Autodesk Fusion 360 part; units mm, degrees
(part 2 of 3)
sketch "Skizze2 (7)" plane through (0, 0, 263) normal (0, 0, 1) x (1, 0, 0) in component "Rear_thread_plate_left_0.15"
  circle A0 centre (22, 84) radius 2.1
  dimension "d573" = 22
  dimension "d574" = 84
  dimension "d575" = 4.2
  measures "d573" horizontal distance of origin A0.centre
  measures "d574" vertical distance of origin A0.centre
  measures "d575" diameter of A0
extrude "M5_pilot_not_thread_geometry" cut sketch "Skizze2 (7)" along normal blind 5 bodies 24 in component "Rear_thread_plate_left_0.15"
ref_plane "Arbeitsebene3" through (0, 0, 263) normal (0, 0, 1) x (1, 0, 0) in component "Rear_thread_plate_left_0.15"
sketch "Skizze3 (9)" plane through (0, 0, 263) normal (0, 0, 1) x (1, 0, 0) in component "Rear_thread_plate_left_0.15"
  circle A0 centre (22, 72) radius 1.5
  dimension "d580" = 22
  dimension "d581" = 72
  dimension "d582" = 3
  measures "d580" horizontal distance of origin A0.centre
  measures "d581" vertical distance of origin A0.centre
  measures "d582" diameter of A0
extrude "Retainer_bore" cut sketch "Skizze3 (9)" along normal blind 5 bodies 24 in component "Rear_thread_plate_left_0.15"
ref_plane "Arbeitsebene4" through (0, 0, 263) normal (0, 0, 1) x (1, 0, 0) in component "Rear_thread_plate_left_0.15"
sketch "Skizze4 (6)" plane through (0, 0, 263) normal (0, 0, 1) x (1, 0, 0) in component "Rear_thread_plate_left_0.15"
  circle A0 centre (22, 96) radius 1.5
  dimension "d587" = 22
  dimension "d588" = 96
  dimension "d589" = 3
  measures "d587" horizontal distance of origin A0.centre
  measures "d588" vertical distance of origin A0.centre
  measures "d589" diameter of A0
extrude "Retainer_bore (1)" cut sketch "Skizze4 (6)" along normal blind 5 bodies 24 in component "Rear_thread_plate_left_0.15"
ref_plane "Arbeitsebene3" through (0, 0, 288) normal (0, 0, 1) x (1, 0, 0) in component "Rear_removable"
sketch "Skizze4 (7)" plane through (0, 0, 288) normal (0, 0, 1) x (1, 0, 0) in component "Rear_removable"
  circle A0 centre (22, 280) radius 2.75
  dimension "d594" = 22
  dimension "d595" = 280
  dimension "d596" = 5.5
  measures "d594" horizontal distance of origin A0.centre
  measures "d595" vertical distance of origin A0.centre
  measures "d596" diameter of A0
extrude "Rear_M5_through_left_0.5" cut sketch "Skizze4 (7)" along normal blind 12 bodies 6 in component "Rear_removable"
ref_plane "Arbeitsebene3" through (0, 0, 268) normal (0, 0, 1) x (1, 0, 0) in component "Rear_cleat_left"
sketch "Skizze4 (8)" plane through (0, 0, 268) normal (0, 0, 1) x (1, 0, 0) in component "Rear_cleat_left"
  circle A0 centre (22, 280) radius 2.75
  dimension "d601" = 22
  dimension "d602" = 280
  dimension "d603" = 5.5
  measures "d601" horizontal distance of origin A0.centre
  measures "d602" vertical distance of origin A0.centre
  measures "d603" diameter of A0
ref_plane "Arbeitsebene1" through (0, 0, 263) normal (0, 0, 1) x (1, 0, 0) in component "Rear_thread_plate_left_0.5"
sketch "Skizze1 (22)" plane through (0, 0, 263) normal (0, 0, 1) x (1, 0, 0) in component "Rear_thread_plate_left_0.5"
  line L0 (12, 260) -> (32, 260)
  line L1 (32, 260) -> (32, 300)
  line L2 (32, 300) -> (12, 300)
  line L3 (12, 300) -> (12, 260)
  dimension "d608" = 12
  dimension "d609" = 260
  dimension "d610" = 20
  dimension "d611" = 40
  constraint horizontal L0
  constraint horizontal L2
  constraint vertical L1
  constraint vertical L3
  measures "d608" horizontal distance of origin L0.start
  measures "d609" vertical distance of origin L0.start
  measures "d610" horizontal distance of L0.start L0.end
  measures "d611" vertical distance of L0.end L1.end
extrude "Steel_plate_M5_tap_after_drilling'" add sketch "Skizze1 (22)" along normal blind 5 separate body makes body 25 in component "Rear_thread_plate_left_0.5"
ref_plane "Arbeitsebene2" through (0, 0, 263) normal (0, 0, 1) x (1, 0, 0) in component "Rear_thread_plate_left_0.5"
sketch "Skizze2 (8)" plane through (0, 0, 263) normal (0, 0, 1) x (1, 0, 0) in component "Rear_thread_plate_left_0.5"
  circle A0 centre (22, 280) radius 2.1
  dimension "d616" = 22
  dimension "d617" = 280
  dimension "d618" = 4.2
  measures "d616" horizontal distance of origin A0.centre
  measures "d617" vertical distance of origin A0.centre
  measures "d618" diameter of A0
extrude "M5_pilot_not_thread_geometry'" cut sketch "Skizze2 (8)" along normal blind 5 bodies 25 in component "Rear_thread_plate_left_0.5"
ref_plane "Arbeitsebene3" through (0, 0, 263) normal (0, 0, 1) x (1, 0, 0) in component "Rear_thread_plate_left_0.5"
sketch "Skizze3 (10)" plane through (0, 0, 263) normal (0, 0, 1) x (1, 0, 0) in component "Rear_thread_plate_left_0.5"
  circle A0 centre (22, 268) radius 1.5
  dimension "d623" = 22
  dimension "d624" = 268
  dimension "d625" = 3
  measures "d623" horizontal distance of origin A0.centre
  measures "d624" vertical distance of origin A0.centre
  measures "d625" diameter of A0
extrude "Retainer_bore'" cut sketch "Skizze3 (10)" along normal blind 5 bodies 25 in component "Rear_thread_plate_left_0.5"
ref_plane "Arbeitsebene4" through (0, 0, 263) normal (0, 0, 1) x (1, 0, 0) in component "Rear_thread_plate_left_0.5"
sketch "Skizze4 (9)" plane through (0, 0, 263) normal (0, 0, 1) x (1, 0, 0) in component "Rear_thread_plate_left_0.5"
  circle A0 centre (22, 292) radius 1.5
  dimension "d630" = 22
  dimension "d631" = 292
  dimension "d632" = 3
  measures "d630" horizontal distance of origin A0.centre
  measures "d631" vertical distance of origin A0.centre
  measures "d632" diameter of A0
extrude "Retainer_bore (1)'" cut sketch "Skizze4 (9)" along normal blind 5 bodies 25 in component "Rear_thread_plate_left_0.5"
ref_plane "Arbeitsebene4" through (0, 0, 288) normal (0, 0, 1) x (1, 0, 0) in component "Rear_removable"
sketch "Skizze5 (4)" plane through (0, 0, 288) normal (0, 0, 1) x (1, 0, 0) in component "Rear_removable"
  circle A0 centre (22, 476) radius 2.75
  dimension "d637" = 22
  dimension "d638" = 476
  dimension "d639" = 5.5
  measures "d637" horizontal distance of origin A0.centre
  measures "d638" vertical distance of origin A0.centre
  measures "d639" diameter of A0
extrude "Rear_M5_through_left_0.85" cut sketch "Skizze5 (4)" along normal blind 12 bodies 6 in component "Rear_removable"
ref_plane "Arbeitsebene4" through (0, 0, 268) normal (0, 0, 1) x (1, 0, 0) in component "Rear_cleat_left"
sketch "Skizze5 (5)" plane through (0, 0, 268) normal (0, 0, 1) x (1, 0, 0) in component "Rear_cleat_left"
  circle A0 centre (22, 476) radius 2.75
  dimension "d644" = 22
  dimension "d645" = 476
  dimension "d646" = 5.5
  measures "d644" horizontal distance of origin A0.centre
  measures "d645" vertical distance of origin A0.centre
  measures "d646" diameter of A0
ref_plane "Arbeitsebene1" through (0, 0, 263) normal (0, 0, 1) x (1, 0, 0) in component "Rear_thread_plate_left_0.85"
sketch "Skizze1 (23)" plane through (0, 0, 263) normal (0, 0, 1) x (1, 0, 0) in component "Rear_thread_plate_left_0.85"
  line L0 (12, 456) -> (32, 456)
  line L1 (32, 456) -> (32, 496)
  line L2 (32, 496) -> (12, 496)
  line L3 (12, 496) -> (12, 456)
  dimension "d651" = 12
  dimension "d652" = 456
  dimension "d653" = 20
  dimension "d654" = 40
  constraint horizontal L0
  constraint horizontal L2
  constraint vertical L1
  constraint vertical L3
  measures "d651" horizontal distance of origin L0.start
  measures "d652" vertical distance of origin L0.start
  measures "d653" horizontal distance of L0.start L0.end
  measures "d654" vertical distance of L0.end L1.end
extrude "Steel_plate_M5_tap_after_drilling''" add sketch "Skizze1 (23)" along normal blind 5 separate body makes body 26 in component "Rear_thread_plate_left_0.85"
ref_plane "Arbeitsebene2" through (0, 0, 263) normal (0, 0, 1) x (1, 0, 0) in component "Rear_thread_plate_left_0.85"
sketch "Skizze2 (9)" plane through (0, 0, 263) normal (0, 0, 1) x (1, 0, 0) in component "Rear_thread_plate_left_0.85"
  circle A0 centre (22, 476) radius 2.1
  dimension "d659" = 22
  dimension "d660" = 476
  dimension "d661" = 4.2
  measures "d659" horizontal distance of origin A0.centre
  measures "d660" vertical distance of origin A0.centre
  measures "d661" diameter of A0
extrude "M5_pilot_not_thread_geometry''" cut sketch "Skizze2 (9)" along normal blind 5 bodies 26 in component "Rear_thread_plate_left_0.85"
ref_plane "Arbeitsebene3" through (0, 0, 263) normal (0, 0, 1) x (1, 0, 0) in component "Rear_thread_plate_left_0.85"
sketch "Skizze3 (11)" plane through (0, 0, 263) normal (0, 0, 1) x (1, 0, 0) in component "Rear_thread_plate_left_0.85"
  circle A0 centre (22, 464) radius 1.5
  dimension "d666" = 22
  dimension "d667" = 464
  dimension "d668" = 3
  measures "d666" horizontal distance of origin A0.centre
  measures "d667" vertical distance of origin A0.centre
  measures "d668" diameter of A0
extrude "Retainer_bore''" cut sketch "Skizze3 (11)" along normal blind 5 bodies 26 in component "Rear_thread_plate_left_0.85"
ref_plane "Arbeitsebene4" through (0, 0, 263) normal (0, 0, 1) x (1, 0, 0) in component "Rear_thread_plate_left_0.85"
sketch "Skizze4 (10)" plane through (0, 0, 263) normal (0, 0, 1) x (1, 0, 0) in component "Rear_thread_plate_left_0.85"
  circle A0 centre (22, 488) radius 1.5
  dimension "d673" = 22
  dimension "d674" = 488
  dimension "d675" = 3
  measures "d673" horizontal distance of origin A0.centre
  measures "d674" vertical distance of origin A0.centre
  measures "d675" diameter of A0
extrude "Retainer_bore (1)''" cut sketch "Skizze4 (10)" along normal blind 5 bodies 26 in component "Rear_thread_plate_left_0.85"
ref_plane "Arbeitsebene5" through (0, 0, 288) normal (0, 0, 1) x (1, 0, 0) in component "Rear_removable"
sketch "Skizze6 (4)" plane through (0, 0, 288) normal (0, 0, 1) x (1, 0, 0) in component "Rear_removable"
  circle A0 centre (308, 84) radius 2.75
  dimension "d680" = 308
  dimension "d681" = 84
  dimension "d682" = 5.5
  measures "d680" horizontal distance of origin A0.centre
  measures "d681" vertical distance of origin A0.centre
  measures "d682" diameter of A0
extrude "Rear_M5_through_right_0.15" cut sketch "Skizze6 (4)" along normal blind 12 bodies 6 in component "Rear_removable"
ref_plane "Arbeitsebene2" through (0, 0, 268) normal (0, 0, 1) x (1, 0, 0) in component "Rear_cleat_right"
sketch "Skizze3 (12)" plane through (0, 0, 268) normal (0, 0, 1) x (1, 0, 0) in component "Rear_cleat_right"
  circle A0 centre (308, 84) radius 2.75
  dimension "d687" = 308
  dimension "d688" = 84
  dimension "d689" = 5.5
  measures "d687" horizontal distance of origin A0.centre
  measures "d688" vertical distance of origin A0.centre
  measures "d689" diameter of A0
ref_plane "Arbeitsebene1" through (0, 0, 263) normal (0, 0, 1) x (1, 0, 0) in component "Rear_thread_plate_right_0.15"
sketch "Skizze1 (24)" plane through (0, 0, 263) normal (0, 0, 1) x (1, 0, 0) in component "Rear_thread_plate_right_0.15"
  line L0 (298, 64) -> (318, 64)
  line L1 (318, 64) -> (318, 104)
  line L2 (318, 104) -> (298, 104)
  line L3 (298, 104) -> (298, 64)
  dimension "d694" = 298
  dimension "d695" = 64
  dimension "d696" = 20
  dimension "d697" = 40
  constraint horizontal L0
  constraint horizontal L2
  constraint vertical L1
  constraint vertical L3
  measures "d694" horizontal distance of origin L0.start
  measures "d695" vertical distance of origin L0.start
  measures "d696" horizontal distance of L0.start L0.end
  measures "d697" vertical distance of L0.end L1.end
extrude "Steel_plate_M5_tap_after_drilling'''" add sketch "Skizze1 (24)" along normal blind 5 separate body makes body 27 in component "Rear_thread_plate_right_0.15"
ref_plane "Arbeitsebene2" through (0, 0, 263) normal (0, 0, 1) x (1, 0, 0) in component "Rear_thread_plate_right_0.15"
sketch "Skizze2 (10)" plane through (0, 0, 263) normal (0, 0, 1) x (1, 0, 0) in component "Rear_thread_plate_right_0.15"
  circle A0 centre (308, 84) radius 2.1
  dimension "d702" = 308
  dimension "d703" = 84
  dimension "d704" = 4.2
  measures "d702" horizontal distance of origin A0.centre
  measures "d703" vertical distance of origin A0.centre
  measures "d704" diameter of A0
extrude "M5_pilot_not_thread_geometry'''" cut sketch "Skizze2 (10)" along normal blind 5 bodies 27 in component "Rear_thread_plate_right_0.15"
ref_plane "Arbeitsebene3" through (0, 0, 263) normal (0, 0, 1) x (1, 0, 0) in component "Rear_thread_plate_right_0.15"
sketch "Skizze3 (13)" plane through (0, 0, 263) normal (0, 0, 1) x (1, 0, 0) in component "Rear_thread_plate_right_0.15"
  circle A0 centre (308, 72) radius 1.5
  dimension "d709" = 308
  dimension "d710" = 72
  dimension "d711" = 3
  measures "d709" horizontal distance of origin A0.centre
  measures "d710" vertical distance of origin A0.centre
  measures "d711" diameter of A0
extrude "Retainer_bore'''" cut sketch "Skizze3 (13)" along normal blind 5 bodies 27 in component "Rear_thread_plate_right_0.15"
ref_plane "Arbeitsebene4" through (0, 0, 263) normal (0, 0, 1) x (1, 0, 0) in component "Rear_thread_plate_right_0.15"
sketch "Skizze4 (11)" plane through (0, 0, 263) normal (0, 0, 1) x (1, 0, 0) in component "Rear_thread_plate_right_0.15"
  circle A0 centre (308, 96) radius 1.5
  dimension "d716" = 308
  dimension "d717" = 96
  dimension "d718" = 3
  measures "d716" horizontal distance of origin A0.centre
  measures "d717" vertical distance of origin A0.centre
  measures "d718" diameter of A0
extrude "Retainer_bore (1)'''" cut sketch "Skizze4 (11)" along normal blind 5 bodies 27 in component "Rear_thread_plate_right_0.15"
ref_plane "Arbeitsebene6" through (0, 0, 288) normal (0, 0, 1) x (1, 0, 0) in component "Rear_removable"
sketch "Skizze7 (4)" plane through (0, 0, 288) normal (0, 0, 1) x (1, 0, 0) in component "Rear_removable"
  circle A0 centre (308, 280) radius 2.75
  dimension "d723" = 308
  dimension "d724" = 280
  dimension "d725" = 5.5
  measures "d723" horizontal distance of origin A0.centre
  measures "d724" vertical distance of origin A0.centre
  measures "d725" diameter of A0
extrude "Rear_M5_through_right_0.5" cut sketch "Skizze7 (4)" along normal blind 12 bodies 6 in component "Rear_removable"
ref_plane "Arbeitsebene3" through (0, 0, 268) normal (0, 0, 1) x (1, 0, 0) in component "Rear_cleat_right"
sketch "Skizze4 (12)" plane through (0, 0, 268) normal (0, 0, 1) x (1, 0, 0) in component "Rear_cleat_right"
  circle A0 centre (308, 280) radius 2.75
  dimension "d730" = 308
  dimension "d731" = 280
  dimension "d732" = 5.5
  measures "d730" horizontal distance of origin A0.centre
  measures "d731" vertical distance of origin A0.centre
  measures "d732" diameter of A0
ref_plane "Arbeitsebene1" through (0, 0, 263) normal (0, 0, 1) x (1, 0, 0) in component "Rear_thread_plate_right_0.5"
sketch "Skizze1 (25)" plane through (0, 0, 263) normal (0, 0, 1) x (1, 0, 0) in component "Rear_thread_plate_right_0.5"
  line L0 (298, 260) -> (318, 260)
  line L1 (318, 260) -> (318, 300)
  line L2 (318, 300) -> (298, 300)
  line L3 (298, 300) -> (298, 260)
  dimension "d737" = 298
  dimension "d738" = 260
  dimension "d739" = 20
  dimension "d740" = 40
  constraint horizontal L0
  constraint horizontal L2
  constraint vertical L1
  constraint vertical L3
  measures "d737" horizontal distance of origin L0.start
  measures "d738" vertical distance of origin L0.start
  measures "d739" horizontal distance of L0.start L0.end
  measures "d740" vertical distance of L0.end L1.end
extrude "Steel_plate_M5_tap_after_drilling''''" add sketch "Skizze1 (25)" along normal blind 5 separate body makes body 28 in component "Rear_thread_plate_right_0.5"
ref_plane "Arbeitsebene2" through (0, 0, 263) normal (0, 0, 1) x (1, 0, 0) in component "Rear_thread_plate_right_0.5"
sketch "Skizze2 (11)" plane through (0, 0, 263) normal (0, 0, 1) x (1, 0, 0) in component "Rear_thread_plate_right_0.5"
  circle A0 centre (308, 280) radius 2.1
  dimension "d745" = 308
  dimension "d746" = 280
  dimension "d747" = 4.2
  measures "d745" horizontal distance of origin A0.centre
  measures "d746" vertical distance of origin A0.centre
  measures "d747" diameter of A0
extrude "M5_pilot_not_thread_geometry''''" cut sketch "Skizze2 (11)" along normal blind 5 bodies 28 in component "Rear_thread_plate_right_0.5"
ref_plane "Arbeitsebene3" through (0, 0, 263) normal (0, 0, 1) x (1, 0, 0) in component "Rear_thread_plate_right_0.5"
sketch "Skizze3 (14)" plane through (0, 0, 263) normal (0, 0, 1) x (1, 0, 0) in component "Rear_thread_plate_right_0.5"
  circle A0 centre (308, 268) radius 1.5
  dimension "d752" = 308
  dimension "d753" = 268
  dimension "d754" = 3
  measures "d752" horizontal distance of origin A0.centre
  measures "d753" vertical distance of origin A0.centre
  measures "d754" diameter of A0
extrude "Retainer_bore''''" cut sketch "Skizze3 (14)" along normal blind 5 bodies 28 in component "Rear_thread_plate_right_0.5"
ref_plane "Arbeitsebene4" through (0, 0, 263) normal (0, 0, 1) x (1, 0, 0) in component "Rear_thread_plate_right_0.5"
sketch "Skizze4 (13)" plane through (0, 0, 263) normal (0, 0, 1) x (1, 0, 0) in component "Rear_thread_plate_right_0.5"
  circle A0 centre (308, 292) radius 1.5
  dimension "d759" = 308
  dimension "d760" = 292
  dimension "d761" = 3
  measures "d759" horizontal distance of origin A0.centre
  measures "d760" vertical distance of origin A0.centre
  measures "d761" diameter of A0
extrude "Retainer_bore (1)''''" cut sketch "Skizze4 (13)" along normal blind 5 bodies 28 in component "Rear_thread_plate_right_0.5"
ref_plane "Arbeitsebene7" through (0, 0, 288) normal (0, 0, 1) x (1, 0, 0) in component "Rear_removable"
sketch "Skizze8 (4)" plane through (0, 0, 288) normal (0, 0, 1) x (1, 0, 0) in component "Rear_removable"
  circle A0 centre (308, 476) radius 2.75
  dimension "d766" = 308
  dimension "d767" = 476
  dimension "d768" = 5.5
  measures "d766" horizontal distance of origin A0.centre
  measures "d767" vertical distance of origin A0.centre
  measures "d768" diameter of A0
extrude "Rear_M5_through_right_0.85" cut sketch "Skizze8 (4)" along normal blind 12 bodies 6 in component "Rear_removable"
ref_plane "Arbeitsebene4" through (0, 0, 268) normal (0, 0, 1) x (1, 0, 0) in component "Rear_cleat_right"
sketch "Skizze5 (6)" plane through (0, 0, 268) normal (0, 0, 1) x (1, 0, 0) in component "Rear_cleat_right"
  circle A0 centre (308, 476) radius 2.75
  dimension "d773" = 308
  dimension "d774" = 476
  dimension "d775" = 5.5
  measures "d773" horizontal distance of origin A0.centre
  measures "d774" vertical distance of origin A0.centre
  measures "d775" diameter of A0
ref_plane "Arbeitsebene1" through (0, 0, 263) normal (0, 0, 1) x (1, 0, 0) in component "Rear_thread_plate_right_0.85"
sketch "Skizze1 (26)" plane through (0, 0, 263) normal (0, 0, 1) x (1, 0, 0) in component "Rear_thread_plate_right_0.85"
  line L0 (298, 456) -> (318, 456)
  line L1 (318, 456) -> (318, 496)
  line L2 (318, 496) -> (298, 496)
  line L3 (298, 496) -> (298, 456)
  dimension "d780" = 298
  dimension "d781" = 456
  dimension "d782" = 20
  dimension "d783" = 40
  constraint horizontal L0
  constraint horizontal L2
  constraint vertical L1
  constraint vertical L3
  measures "d780" horizontal distance of origin L0.start
  measures "d781" vertical distance of origin L0.start
  measures "d782" horizontal distance of L0.start L0.end
  measures "d783" vertical distance of L0.end L1.end
extrude "Steel_plate_M5_tap_after_drilling'''''" add sketch "Skizze1 (26)" along normal blind 5 separate body makes body 29 in component "Rear_thread_plate_right_0.85"
ref_plane "Arbeitsebene2" through (0, 0, 263) normal (0, 0, 1) x (1, 0, 0) in component "Rear_thread_plate_right_0.85"
sketch "Skizze2 (12)" plane through (0, 0, 263) normal (0, 0, 1) x (1, 0, 0) in component "Rear_thread_plate_right_0.85"
  circle A0 centre (308, 476) radius 2.1
  dimension "d788" = 308
  dimension "d789" = 476
  dimension "d790" = 4.2
  measures "d788" horizontal distance of origin A0.centre
  measures "d789" vertical distance of origin A0.centre
  measures "d790" diameter of A0
extrude "M5_pilot_not_thread_geometry'''''" cut sketch "Skizze2 (12)" along normal blind 5 bodies 29 in component "Rear_thread_plate_right_0.85"
ref_plane "Arbeitsebene3" through (0, 0, 263) normal (0, 0, 1) x (1, 0, 0) in component "Rear_thread_plate_right_0.85"
sketch "Skizze3 (15)" plane through (0, 0, 263) normal (0, 0, 1) x (1, 0, 0) in component "Rear_thread_plate_right_0.85"
  circle A0 centre (308, 464) radius 1.5
  dimension "d795" = 308
  dimension "d796" = 464
  dimension "d797" = 3
  measures "d795" horizontal distance of origin A0.centre
  measures "d796" vertical distance of origin A0.centre
  measures "d797" diameter of A0
extrude "Retainer_bore'''''" cut sketch "Skizze3 (15)" along normal blind 5 bodies 29 in component "Rear_thread_plate_right_0.85"
ref_plane "Arbeitsebene4" through (0, 0, 263) normal (0, 0, 1) x (1, 0, 0) in component "Rear_thread_plate_right_0.85"
sketch "Skizze4 (14)" plane through (0, 0, 263) normal (0, 0, 1) x (1, 0, 0) in component "Rear_thread_plate_right_0.85"
  circle A0 centre (308, 488) radius 1.5
  dimension "d802" = 308
  dimension "d803" = 488
  dimension "d804" = 3
  measures "d802" horizontal distance of origin A0.centre
  measures "d803" vertical distance of origin A0.centre
  measures "d804" diameter of A0
extrude "Retainer_bore (1)'''''" cut sketch "Skizze4 (14)" along normal blind 5 bodies 29 in component "Rear_thread_plate_right_0.85"
ref_plane "Arbeitsebene8" through (0, 0, 288) normal (0, 0, 1) x (1, 0, 0) in component "Rear_removable"
sketch "Skizze9 (4)" plane through (0, 0, 288) normal (0, 0, 1) x (1, 0, 0) in component "Rear_removable"
  circle A0 centre (89.1, 22) radius 2.75
  dimension "d809" = 89.1
  dimension "d810" = 22
  dimension "d811" = 5.5
  measures "d809" horizontal distance of origin A0.centre
  measures "d810" vertical distance of origin A0.centre
  measures "d811" diameter of A0
extrude "Rear_M5_through_bottom_0.27" cut sketch "Skizze9 (4)" along normal blind 12 bodies 6 in component "Rear_removable"
ref_plane "Arbeitsebene2" through (0, 0, 268) normal (0, 0, 1) x (1, 0, 0) in component "Rear_cleat_bottom"
sketch "Skizze3 (16)" plane through (0, 0, 268) normal (0, 0, 1) x (1, 0, 0) in component "Rear_cleat_bottom"
  circle A0 centre (89.1, 22) radius 2.75
  dimension "d816" = 89.1
  dimension "d817" = 22
  dimension "d818" = 5.5
  measures "d816" horizontal distance of origin A0.centre
  measures "d817" vertical distance of origin A0.centre
  measures "d818" diameter of A0
extrude "Rear_M5_through_bottom_0.27'" cut sketch "Skizze3 (16)" along normal blind 20 bodies 11 in component "Rear_cleat_bottom"
ref_plane "Arbeitsebene1" through (0, 0, 263) normal (0, 0, 1) x (1, 0, 0) in component "Rear_thread_plate_bottom_0.27"
sketch "Skizze1 (27)" plane through (0, 0, 263) normal (0, 0, 1) x (1, 0, 0) in component "Rear_thread_plate_bottom_0.27"
  line L0 (69.1, 12) -> (109.1, 12)
  line L1 (109.1, 12) -> (109.1, 32)
  line L2 (109.1, 32) -> (69.1, 32)
  line L3 (69.1, 32) -> (69.1, 12)
  dimension "d823" = 69.1
  dimension "d824" = 12
  dimension "d825" = 40
  dimension "d826" = 20
  constraint horizontal L0
  constraint horizontal L2
  constraint vertical L1
  constraint vertical L3
  measures "d823" horizontal distance of origin L0.start
  measures "d824" vertical distance of origin L0.start
  measures "d825" horizontal distance of L0.start L0.end
  measures "d826" vertical distance of L0.end L1.end
extrude "Steel_plate_M5_tap_after_drilling''''''" add sketch "Skizze1 (27)" along normal blind 5 separate body makes body 30 in component "Rear_thread_plate_bottom_0.27"
ref_plane "Arbeitsebene2" through (0, 0, 263) normal (0, 0, 1) x (1, 0, 0) in component "Rear_thread_plate_bottom_0.27"
sketch "Skizze2 (13)" plane through (0, 0, 263) normal (0, 0, 1) x (1, 0, 0) in component "Rear_thread_plate_bottom_0.27"
  circle A0 centre (89.1, 22) radius 2.1
  dimension "d831" = 89.1
  dimension "d832" = 22
  dimension "d833" = 4.2
  measures "d831" horizontal distance of origin A0.centre
  measures "d832" vertical distance of origin A0.centre
  measures "d833" diameter of A0
extrude "M5_pilot_not_thread_geometry''''''" cut sketch "Skizze2 (13)" along normal blind 5 bodies 30 in component "Rear_thread_plate_bottom_0.27"
ref_plane "Arbeitsebene3" through (0, 0, 263) normal (0, 0, 1) x (1, 0, 0) in component "Rear_thread_plate_bottom_0.27"
sketch "Skizze3 (17)" plane through (0, 0, 263) normal (0, 0, 1) x (1, 0, 0) in component "Rear_thread_plate_bottom_0.27"
  circle A0 centre (77.1, 22) radius 1.5
  dimension "d838" = 77.1
  dimension "d839" = 22
  dimension "d840" = 3
  measures "d838" horizontal distance of origin A0.centre
  measures "d839" vertical distance of origin A0.centre
  measures "d840" diameter of A0
extrude "Retainer_bore''''''" cut sketch "Skizze3 (17)" along normal blind 5 bodies 30 in component "Rear_thread_plate_bottom_0.27"
ref_plane "Arbeitsebene4" through (0, 0, 263) normal (0, 0, 1) x (1, 0, 0) in component "Rear_thread_plate_bottom_0.27"
sketch "Skizze4 (15)" plane through (0, 0, 263) normal (0, 0, 1) x (1, 0, 0) in component "Rear_thread_plate_bottom_0.27"
  circle A0 centre (101.1, 22) radius 1.5
  dimension "d845" = 101.1
  dimension "d846" = 22
  dimension "d847" = 3
  measures "d845" horizontal distance of origin A0.centre
  measures "d846" vertical distance of origin A0.centre
  measures "d847" diameter of A0
extrude "Retainer_bore (1)''''''" cut sketch "Skizze4 (15)" along normal blind 5 bodies 30 in component "Rear_thread_plate_bottom_0.27"
ref_plane "Arbeitsebene9" through (0, 0, 288) normal (0, 0, 1) x (1, 0, 0) in component "Rear_removable"
sketch "Skizze10 (4)" plane through (0, 0, 288) normal (0, 0, 1) x (1, 0, 0) in component "Rear_removable"
  circle A0 centre (240.9, 22) radius 2.75
  dimension "d852" = 240.9
  dimension "d853" = 22
  dimension "d854" = 5.5
  measures "d852" horizontal distance of origin A0.centre
  measures "d853" vertical distance of origin A0.centre
  measures "d854" diameter of A0
extrude "Rear_M5_through_bottom_0.73" cut sketch "Skizze10 (4)" along normal blind 12 bodies 6 in component "Rear_removable"
ref_plane "Arbeitsebene3" through (0, 0, 268) normal (0, 0, 1) x (1, 0, 0) in component "Rear_cleat_bottom"
sketch "Skizze4 (16)" plane through (0, 0, 268) normal (0, 0, 1) x (1, 0, 0) in component "Rear_cleat_bottom"
  circle A0 centre (240.9, 22) radius 2.75
  dimension "d859" = 240.9
  dimension "d860" = 22
  dimension "d861" = 5.5
  measures "d859" horizontal distance of origin A0.centre
  measures "d860" vertical distance of origin A0.centre
  measures "d861" diameter of A0
extrude "Rear_M5_through_bottom_0.73'" cut sketch "Skizze4 (16)" along normal blind 20 bodies 11 in component "Rear_cleat_bottom"
ref_plane "Arbeitsebene1" through (0, 0, 263) normal (0, 0, 1) x (1, 0, 0) in component "Rear_thread_plate_bottom_0.73"
sketch "Skizze1 (28)" plane through (0, 0, 263) normal (0, 0, 1) x (1, 0, 0) in component "Rear_thread_plate_bottom_0.73"
  line L0 (220.9, 12) -> (260.9, 12)
  line L1 (260.9, 12) -> (260.9, 32)
  line L2 (260.9, 32) -> (220.9, 32)
  line L3 (220.9, 32) -> (220.9, 12)
  dimension "d866" = 220.9
  dimension "d867" = 12
  dimension "d868" = 40
  dimension "d869" = 20
  constraint horizontal L0
  constraint horizontal L2
  constraint vertical L1
  constraint vertical L3
  measures "d866" horizontal distance of origin L0.start
  measures "d867" vertical distance of origin L0.start
  measures "d868" horizontal distance of L0.start L0.end
  measures "d869" vertical distance of L0.end L1.end
extrude "Steel_plate_M5_tap_after_drilling'''''''" add sketch "Skizze1 (28)" along normal blind 5 separate body makes body 31 in component "Rear_thread_plate_bottom_0.73"
ref_plane "Arbeitsebene2" through (0, 0, 263) normal (0, 0, 1) x (1, 0, 0) in component "Rear_thread_plate_bottom_0.73"
sketch "Skizze2 (14)" plane through (0, 0, 263) normal (0, 0, 1) x (1, 0, 0) in component "Rear_thread_plate_bottom_0.73"
  circle A0 centre (240.9, 22) radius 2.1
  dimension "d874" = 240.9
  dimension "d875" = 22
  dimension "d876" = 4.2
  measures "d874" horizontal distance of origin A0.centre
  measures "d875" vertical distance of origin A0.centre
  measures "d876" diameter of A0
extrude "M5_pilot_not_thread_geometry'''''''" cut sketch "Skizze2 (14)" along normal blind 5 bodies 31 in component "Rear_thread_plate_bottom_0.73"
ref_plane "Arbeitsebene3" through (0, 0, 263) normal (0, 0, 1) x (1, 0, 0) in component "Rear_thread_plate_bottom_0.73"
sketch "Skizze3 (18)" plane through (0, 0, 263) normal (0, 0, 1) x (1, 0, 0) in component "Rear_thread_plate_bottom_0.73"
  circle A0 centre (228.9, 22) radius 1.5
  dimension "d881" = 228.9
  dimension "d882" = 22
  dimension "d883" = 3
  measures "d881" horizontal distance of origin A0.centre
  measures "d882" vertical distance of origin A0.centre
  measures "d883" diameter of A0
extrude "Retainer_bore'''''''" cut sketch "Skizze3 (18)" along normal blind 5 bodies 31 in component "Rear_thread_plate_bottom_0.73"
ref_plane "Arbeitsebene4" through (0, 0, 263) normal (0, 0, 1) x (1, 0, 0) in component "Rear_thread_plate_bottom_0.73"
sketch "Skizze4 (17)" plane through (0, 0, 263) normal (0, 0, 1) x (1, 0, 0) in component "Rear_thread_plate_bottom_0.73"
  circle A0 centre (252.9, 22) radius 1.5
  dimension "d888" = 252.9
  dimension "d889" = 22
  dimension "d890" = 3
  measures "d888" horizontal distance of origin A0.centre
  measures "d889" vertical distance of origin A0.centre
  measures "d890" diameter of A0
extrude "Retainer_bore (1)'''''''" cut sketch "Skizze4 (17)" along normal blind 5 bodies 31 in component "Rear_thread_plate_bottom_0.73"
ref_plane "Arbeitsebene10" through (0, 0, 288) normal (0, 0, 1) x (1, 0, 0) in component "Rear_removable"
sketch "Skizze11 (3)" plane through (0, 0, 288) normal (0, 0, 1) x (1, 0, 0) in component "Rear_removable"
  circle A0 centre (89.1, 538) radius 2.75
  dimension "d895" = 89.1
  dimension "d896" = 538
  dimension "d897" = 5.5
  measures "d895" horizontal distance of origin A0.centre
  measures "d896" vertical distance of origin A0.centre
  measures "d897" diameter of A0
extrude "Rear_M5_through_top_0.27" cut sketch "Skizze11 (3)" along normal blind 12 bodies 6 in component "Rear_removable"
ref_plane "Arbeitsebene2" through (0, 0, 268) normal (0, 0, 1) x (1, 0, 0) in component "Rear_cleat_top"
sketch "Skizze3 (19)" plane through (0, 0, 268) normal (0, 0, 1) x (1, 0, 0) in component "Rear_cleat_top"
  circle A0 centre (89.1, 538) radius 2.75
  dimension "d902" = 89.1
  dimension "d903" = 538
  dimension "d904" = 5.5
  measures "d902" horizontal distance of origin A0.centre
  measures "d903" vertical distance of origin A0.centre
  measures "d904" diameter of A0
extrude "Rear_M5_through_top_0.27'" cut sketch "Skizze3 (19)" along normal blind 20 bodies 12 in component "Rear_cleat_top"
ref_plane "Arbeitsebene1" through (0, 0, 263) normal (0, 0, 1) x (1, 0, 0) in component "Rear_thread_plate_top_0.27"
sketch "Skizze1 (29)" plane through (0, 0, 263) normal (0, 0, 1) x (1, 0, 0) in component "Rear_thread_plate_top_0.27"
  line L0 (69.1, 528) -> (109.1, 528)
  line L1 (109.1, 528) -> (109.1, 548)
  line L2 (109.1, 548) -> (69.1, 548)
  line L3 (69.1, 548) -> (69.1, 528)
  dimension "d909" = 69.1
  dimension "d910" = 528
  dimension "d911" = 40
  dimension "d912" = 20
  constraint horizontal L0
  constraint horizontal L2
  constraint vertical L1
  constraint vertical L3
  measures "d909" horizontal distance of origin L0.start
  measures "d910" vertical distance of origin L0.start
  measures "d911" horizontal distance of L0.start L0.end
  measures "d912" vertical distance of L0.end L1.end
extrude "Steel_plate_M5_tap_after_drilling''''''''" add sketch "Skizze1 (29)" along normal blind 5 separate body makes body 32 in component "Rear_thread_plate_top_0.27"
ref_plane "Arbeitsebene2" through (0, 0, 263) normal (0, 0, 1) x (1, 0, 0) in component "Rear_thread_plate_top_0.27"
sketch "Skizze2 (15)" plane through (0, 0, 263) normal (0, 0, 1) x (1, 0, 0) in component "Rear_thread_plate_top_0.27"
  circle A0 centre (89.1, 538) radius 2.1
  dimension "d917" = 89.1
  dimension "d918" = 538
  dimension "d919" = 4.2
  measures "d917" horizontal distance of origin A0.centre
  measures "d918" vertical distance of origin A0.centre
  measures "d919" diameter of A0
extrude "M5_pilot_not_thread_geometry''''''''" cut sketch "Skizze2 (15)" along normal blind 5 bodies 32 in component "Rear_thread_plate_top_0.27"
ref_plane "Arbeitsebene3" through (0, 0, 263) normal (0, 0, 1) x (1, 0, 0) in component "Rear_thread_plate_top_0.27"
sketch "Skizze3 (20)" plane through (0, 0, 263) normal (0, 0, 1) x (1, 0, 0) in component "Rear_thread_plate_top_0.27"
  circle A0 centre (77.1, 538) radius 1.5
  dimension "d924" = 77.1
  dimension "d925" = 538
  dimension "d926" = 3
  measures "d924" horizontal distance of origin A0.centre
  measures "d925" vertical distance of origin A0.centre
  measures "d926" diameter of A0
extrude "Retainer_bore''''''''" cut sketch "Skizze3 (20)" along normal blind 5 bodies 32 in component "Rear_thread_plate_top_0.27"
ref_plane "Arbeitsebene4" through (0, 0, 263) normal (0, 0, 1) x (1, 0, 0) in component "Rear_thread_plate_top_0.27"
sketch "Skizze4 (18)" plane through (0, 0, 263) normal (0, 0, 1) x (1, 0, 0) in component "Rear_thread_plate_top_0.27"
  circle A0 centre (101.1, 538) radius 1.5
  dimension "d931" = 101.1
  dimension "d932" = 538
  dimension "d933" = 3
  measures "d931" horizontal distance of origin A0.centre
  measures "d932" vertical distance of origin A0.centre
  measures "d933" diameter of A0
extrude "Retainer_bore (1)''''''''" cut sketch "Skizze4 (18)" along normal blind 5 bodies 32 in component "Rear_thread_plate_top_0.27"
ref_plane "Arbeitsebene11" through (0, 0, 288) normal (0, 0, 1) x (1, 0, 0) in component "Rear_removable"
sketch "Skizze12 (3)" plane through (0, 0, 288) normal (0, 0, 1) x (1, 0, 0) in component "Rear_removable"
  circle A0 centre (240.9, 538) radius 2.75
  dimension "d938" = 240.9
  dimension "d939" = 538
  dimension "d940" = 5.5
  measures "d938" horizontal distance of origin A0.centre
  measures "d939" vertical distance of origin A0.centre
  measures "d940" diameter of A0
extrude "Rear_M5_through_top_0.73" cut sketch "Skizze12 (3)" along normal blind 12 bodies 6 in component "Rear_removable"
ref_plane "Arbeitsebene3" through (0, 0, 268) normal (0, 0, 1) x (1, 0, 0) in component "Rear_cleat_top"
sketch "Skizze4 (19)" plane through (0, 0, 268) normal (0, 0, 1) x (1, 0, 0) in component "Rear_cleat_top"
  circle A0 centre (240.9, 538) radius 2.75
  dimension "d945" = 240.9
  dimension "d946" = 538
  dimension "d947" = 5.5
  measures "d945" horizontal distance of origin A0.centre
  measures "d946" vertical distance of origin A0.centre
  measures "d947" diameter of A0
extrude "Rear_M5_through_top_0.73'" cut sketch "Skizze4 (19)" along normal blind 20 bodies 12 in component "Rear_cleat_top"
ref_plane "Arbeitsebene1" through (0, 0, 263) normal (0, 0, 1) x (1, 0, 0) in component "Rear_thread_plate_top_0.73"
sketch "Skizze1 (30)" plane through (0, 0, 263) normal (0, 0, 1) x (1, 0, 0) in component "Rear_thread_plate_top_0.73"
  line L0 (220.9, 528) -> (260.9, 528)
  line L1 (260.9, 528) -> (260.9, 548)
  line L2 (260.9, 548) -> (220.9, 548)
  line L3 (220.9, 548) -> (220.9, 528)
  dimension "d952" = 220.9
  dimension "d953" = 528
  dimension "d954" = 40
  dimension "d955" = 20
  constraint horizontal L0
  constraint horizontal L2
  constraint vertical L1
  constraint vertical L3
  measures "d952" horizontal distance of origin L0.start
  measures "d953" vertical distance of origin L0.start
  measures "d954" horizontal distance of L0.start L0.end
  measures "d955" vertical distance of L0.end L1.end
extrude "Steel_plate_M5_tap_after_drilling'''''''''" add sketch "Skizze1 (30)" along normal blind 5 separate body makes body 33 in component "Rear_thread_plate_top_0.73"
ref_plane "Arbeitsebene2" through (0, 0, 263) normal (0, 0, 1) x (1, 0, 0) in component "Rear_thread_plate_top_0.73"
sketch "Skizze2 (16)" plane through (0, 0, 263) normal (0, 0, 1) x (1, 0, 0) in component "Rear_thread_plate_top_0.73"
  circle A0 centre (240.9, 538) radius 2.1
  dimension "d960" = 240.9
  dimension "d961" = 538
  dimension "d962" = 4.2
  measures "d960" horizontal distance of origin A0.centre
  measures "d961" vertical distance of origin A0.centre
  measures "d962" diameter of A0
extrude "M5_pilot_not_thread_geometry'''''''''" cut sketch "Skizze2 (16)" along normal blind 5 bodies 33 in component "Rear_thread_plate_top_0.73"
ref_plane "Arbeitsebene3" through (0, 0, 263) normal (0, 0, 1) x (1, 0, 0) in component "Rear_thread_plate_top_0.73"
sketch "Skizze3 (21)" plane through (0, 0, 263) normal (0, 0, 1) x (1, 0, 0) in component "Rear_thread_plate_top_0.73"
  circle A0 centre (228.9, 538) radius 1.5
  dimension "d967" = 228.9
  dimension "d968" = 538
  dimension "d969" = 3
  measures "d967" horizontal distance of origin A0.centre
  measures "d968" vertical distance of origin A0.centre
  measures "d969" diameter of A0
extrude "Retainer_bore'''''''''" cut sketch "Skizze3 (21)" along normal blind 5 bodies 33 in component "Rear_thread_plate_top_0.73"
ref_plane "Arbeitsebene4" through (0, 0, 263) normal (0, 0, 1) x (1, 0, 0) in component "Rear_thread_plate_top_0.73"
sketch "Skizze4 (20)" plane through (0, 0, 263) normal (0, 0, 1) x (1, 0, 0) in component "Rear_thread_plate_top_0.73"
  circle A0 centre (252.9, 538) radius 1.5
  dimension "d974" = 252.9
  dimension "d975" = 538
  dimension "d976" = 3
  measures "d974" horizontal distance of origin A0.centre
  measures "d975" vertical distance of origin A0.centre
  measures "d976" diameter of A0
extrude "Retainer_bore (1)'''''''''" cut sketch "Skizze4 (20)" along normal blind 5 bodies 33 in component "Rear_thread_plate_top_0.73"
ref_plane "Arbeitsebene12" through (0, 0, 288) normal (0, 0, 1) x (1, 0, 0) in component "Rear_removable"
sketch "Skizze13 (3)" plane through (0, 0, 288) normal (0, 0, 1) x (1, 0, 0) in component "Rear_removable"
  line L0 (14, 14) -> (316, 14)
  line L1 (316, 14) -> (316, 546)
  line L2 (316, 546) -> (14, 546)
  line L3 (14, 546) -> (14, 14)
  line L4 (18, 18) -> (312, 18)
  line L5 (312, 18) -> (312, 542)
  line L6 (312, 542) -> (18, 542)
  line L7 (18, 542) -> (18, 18)
extrude "Gasket_recess_untested" cut sketch "Skizze13 (3)" along normal blind 1 bodies 6 in component "Rear_removable"
extrude "Extrusion4" cut sketch "Skizze2 (6)" along normal blind 20 bodies 14 in component "Service_floor"
extrude "Extrusion5" cut sketch "Skizze3 (6)" along normal blind 20 bodies 14 in component "Service_floor"
sketch "Skizze4 (21)" plane through (12, 0, 0) normal (1, 0, 0) x (0, 1, 0) in component "Side_left"
  line L0 (0, 0) -> (560, 0)
  line L1 (560, 0) -> (560, 300)
  line L2 (560, 300) -> (0, 300)
  line L3 (0, 300) -> (0, 0)
sketch "Skizze4 (22)" plane through (330, 0, 0) normal (1, 0, 0) x (0, 1, 0) in component "Side_right"
  line L0 (0, 0) -> (560, 0)
  line L1 (560, 0) -> (560, 300)
  line L2 (560, 300) -> (0, 300)
  line L3 (0, 300) -> (0, 0)
sketch "Skizze4 (23)" plane through (0, 12, 0) normal (0, 1, 0) x (-1, 0, 0) in component "Bottom"
  line L0 (-318, 0) -> (-12, 0)
  line L1 (-12, 0) -> (-12, 300)
  line L2 (-12, 300) -> (-318, 300)
  line L3 (-318, 300) -> (-318, 0)
sketch "Skizze4 (24)" plane through (0, 560, 0) normal (0, 1, 0) x (-1, 0, 0) in component "Top"
  line L0 (-318, 0) -> (-12, 0)
  line L1 (-12, 0) -> (-12, 300)
  line L2 (-12, 300) -> (-318, 300)
  line L3 (-318, 300) -> (-318, 0)
sketch "Skizze20" plane through (0, 0, 0) normal (0, 0, -1) x (-1, 0, 0) in component "Baffle"
  circle A0 centre (-222, 413) radius 2.25
  circle A1 centre (-108, 413) radius 2.25
  circle A2 centre (-165, 138.1) radius 2.75
  circle A3 centre (-43.1, 260) radius 2.75
  circle A4 centre (-78.8037, 346.1963) radius 2.75
  circle A5 centre (-165, 381.9) radius 2.75
  circle A6 centre (-251.1963, 346.1963) radius 2.75
  circle A7 centre (-286.9, 260) radius 2.75
  line L0 (-217, 522) -> (-113, 522)
  line L1 (-113, 522) -> (-113, 418)
  line L2 (-113, 418) -> (-217, 418)
  line L3 (-217, 418) -> (-217, 522)
  circle A8 centre (-165, 70) radius 48.9864
  circle A9 centre (-165, 260) radius 117.15
  line L4 (-12, 12) -> (-12, 548)
  line L5 (-12, 548) -> (-318, 548)
  line L6 (-318, 548) -> (-318, 12)
  line L7 (-318, 12) -> (-12, 12)
  circle A10 centre (-78.8037, 173.8037) radius 2.75
  circle A11 centre (-251.1963, 173.8037) radius 2.75
  circle A12 centre (-108, 527) radius 2.25
  circle A13 centre (-222, 527) radius 2.25
sketch "Skizze15 (3)" plane through (0, 0, 300) normal (0, 0, 1) x (1, 0, 0) in component "Rear_removable"
  circle A0 centre (89.1, 538) radius 2.75
  line L0 (12, 548) -> (12, 12)
  line L1 (12, 12) -> (318, 12)
  line L2 (318, 12) -> (318, 548)
  line L3 (318, 548) -> (12, 548)
  circle A1 centre (22, 84) radius 2.75
  circle A2 centre (22, 280) radius 2.75
  circle A3 centre (22, 476) radius 2.75
  circle A4 centre (308, 84) radius 2.75
  circle A5 centre (308, 280) radius 2.75
  circle A6 centre (308, 476) radius 2.75
  circle A7 centre (89.1, 22) radius 2.75
  circle A8 centre (240.9, 22) radius 2.75
  circle A9 centre (240.9, 538) radius 2.75
sketch "Skizze19" plane through (0, 0, 24) normal (0, 0, 1) x (1, 0, 0) in component "Baffle_inner_lamination"
  circle A0 centre (222, 413) radius 2.25
  circle A1 centre (108, 413) radius 2.25
  circle A2 centre (165, 138.1) radius 2.75
  circle A3 centre (43.1, 260) radius 2.75
  circle A4 centre (78.8037, 346.1963) radius 2.75
  circle A5 centre (165, 381.9) radius 2.75
  circle A6 centre (251.1963, 346.1963) radius 2.75
  circle A7 centre (286.9, 260) radius 2.75
  line L0 (113, 522) -> (217, 522)
  line L1 (217, 522) -> (217, 418)
  line L2 (217, 418) -> (113, 418)
  line L3 (113, 418) -> (113, 522)
  circle A8 centre (165, 70) radius 48.9864
  circle A9 centre (165, 260) radius 117.15
  line L4 (12, 548) -> (12, 12)
  line L5 (12, 12) -> (318, 12)
  line L6 (318, 12) -> (318, 548)
  line L7 (318, 548) -> (12, 548)
  circle A10 centre (78.8037, 173.8037) radius 2.75
  circle A11 centre (251.1963, 173.8037) radius 2.75
  circle A12 centre (108, 527) radius 2.25
  circle A13 centre (222, 527) radius 2.25
sketch "Skizze13 (4)" plane through (0, 0, 27) normal (0, 0, 1) x (1, 0, 0) in component "LF_steel_backing_ring_candidate"
  circle A0 centre (165, 138.1) radius 2.75
  circle A1 centre (78.8037, 173.8037) radius 2.75
  circle A2 centre (43.1, 260) radius 2.75
  circle A3 centre (78.8037, 346.1963) radius 2.75
  circle A4 centre (165, 381.9) radius 2.75
  circle A5 centre (251.1963, 346.1963) radius 2.75
  circle A6 centre (286.9, 260) radius 2.75
  circle A7 centre (165, 260) radius 110
  circle A8 centre (165, 260) radius 140
  circle A9 centre (251.1963, 173.8037) radius 2.75
sketch "Skizze7 (5)" plane through (0, 0, 288) normal (0, 0, 1) x (1, 0, 0) in component "Rear_cleat_left"
  line L0 (12, 548) -> (12, 12)
  line L1 (12, 12) -> (32, 12)
  line L2 (32, 12) -> (32, 548)
  line L3 (32, 548) -> (12, 548)
sketch "Skizze7 (6)" plane through (0, 0, 288) normal (0, 0, 1) x (1, 0, 0) in component "Rear_cleat_right"
  line L0 (298, 548) -> (298, 12)
  line L1 (298, 12) -> (318, 12)
  line L2 (318, 12) -> (318, 548)
  line L3 (318, 548) -> (298, 548)
sketch "Skizze6 (5)" plane through (0, 0, 288) normal (0, 0, 1) x (1, 0, 0) in component "Rear_cleat_bottom"
  circle A0 centre (240.9, 22) radius 2.75
  circle A1 centre (89.1, 22) radius 2.75
  line L0 (32, 32) -> (32, 12)
  line L1 (32, 12) -> (298, 12)
  line L2 (298, 12) -> (298, 32)
  line L3 (298, 32) -> (32, 32)
sketch "Skizze6 (6)" plane through (0, 0, 288) normal (0, 0, 1) x (1, 0, 0) in component "Rear_cleat_top"
  circle A0 centre (240.9, 538) radius 2.75
  circle A1 centre (89.1, 538) radius 2.75
  line L0 (32, 548) -> (32, 528)
  line L1 (32, 528) -> (298, 528)
  line L2 (298, 528) -> (298, 548)
  line L3 (298, 548) -> (32, 548)
sketch "Skizze4 (25)" plane through (0, 0, 177.9015) normal (0, 0, 1) x (1, 0, 0) in component "Service_partition"
  line L0 (12, 548) -> (12, 362)
  line L1 (12, 362) -> (318, 362)
  line L2 (318, 362) -> (318, 548)
  line L3 (318, 548) -> (12, 548)
sketch "Skizze6 (7)" plane through (0, 350, 0) normal (0, -1, 0) x (1, 0, 0) in component "Service_floor"
  line L0 (318, 268) -> (298, 268)
  line L1 (298, 268) -> (298, 288)
  line L2 (298, 288) -> (32, 288)
  line L3 (32, 288) -> (32, 268)
  line L4 (32, 268) -> (12, 268)
  line L5 (12, 268) -> (12, 165.9015)
  line L6 (12, 165.9015) -> (318, 165.9015)
  line L7 (318, 165.9015) -> (318, 268)
sketch "Skizze4 (26)" plane through (0, 0, 212) normal (0, 0, 1) x (1, 0, 0) in component "Brace_lower"
  line L0 (12, 160) -> (12, 140)
  line L1 (12, 140) -> (318, 140)
  line L2 (318, 140) -> (318, 160)
  line L3 (318, 160) -> (12, 160)
sketch "Skizze6 (8)" plane through (0, 0, 268) normal (0, 0, 1) x (1, 0, 0) in component "Rear_thread_plate_left_0.15"
  circle A0 centre (22, 96) radius 1.5
  circle A1 centre (22, 72) radius 1.5
  circle A2 centre (22, 84) radius 2.1
  line L0 (12, 104) -> (12, 64)
  line L1 (12, 64) -> (32, 64)
  line L2 (32, 64) -> (32, 104)
  line L3 (32, 104) -> (12, 104)
sketch "Skizze6 (9)" plane through (0, 0, 268) normal (0, 0, 1) x (1, 0, 0) in component "Rear_thread_plate_left_0.5"
  circle A0 centre (22, 292) radius 1.5
  circle A1 centre (22, 268) radius 1.5
  circle A2 centre (22, 280) radius 2.1
  line L0 (12, 300) -> (12, 260)
  line L1 (12, 260) -> (32, 260)
  line L2 (32, 260) -> (32, 300)
  line L3 (32, 300) -> (12, 300)
sketch "Skizze6 (10)" plane through (0, 0, 268) normal (0, 0, 1) x (1, 0, 0) in component "Rear_thread_plate_left_0.85"
  circle A0 centre (22, 488) radius 1.5
  circle A1 centre (22, 464) radius 1.5
  circle A2 centre (22, 476) radius 2.1
  line L0 (12, 496) -> (12, 456)
  line L1 (12, 456) -> (32, 456)
  line L2 (32, 456) -> (32, 496)
  line L3 (32, 496) -> (12, 496)
sketch "Skizze6 (11)" plane through (0, 0, 268) normal (0, 0, 1) x (1, 0, 0) in component "Rear_thread_plate_right_0.15"
  circle A0 centre (308, 96) radius 1.5
  circle A1 centre (308, 72) radius 1.5
  circle A2 centre (308, 84) radius 2.1
  line L0 (298, 104) -> (298, 64)
  line L1 (298, 64) -> (318, 64)
  line L2 (318, 64) -> (318, 104)
  line L3 (318, 104) -> (298, 104)
sketch "Skizze6 (12)" plane through (0, 0, 268) normal (0, 0, 1) x (1, 0, 0) in component "Rear_thread_plate_right_0.5"
  circle A0 centre (308, 292) radius 1.5
  circle A1 centre (308, 268) radius 1.5
  circle A2 centre (308, 280) radius 2.1
  line L0 (298, 300) -> (298, 260)
  line L1 (298, 260) -> (318, 260)
  line L2 (318, 260) -> (318, 300)
  line L3 (318, 300) -> (298, 300)
sketch "Skizze6 (13)" plane through (0, 0, 268) normal (0, 0, 1) x (1, 0, 0) in component "Rear_thread_plate_right_0.85"
  circle A0 centre (308, 488) radius 1.5
  circle A1 centre (308, 464) radius 1.5
  circle A2 centre (308, 476) radius 2.1
  line L0 (298, 496) -> (298, 456)
  line L1 (298, 456) -> (318, 456)
  line L2 (318, 456) -> (318, 496)
  line L3 (318, 496) -> (298, 496)
sketch "Skizze6 (14)" plane through (0, 0, 268) normal (0, 0, 1) x (1, 0, 0) in component "Rear_thread_plate_bottom_0.27"
  circle A0 centre (101.1, 22) radius 1.5
  circle A1 centre (77.1, 22) radius 1.5
  circle A2 centre (89.1, 22) radius 2.1
  line L0 (69.1, 32) -> (69.1, 12)
  line L1 (69.1, 12) -> (109.1, 12)
  line L2 (109.1, 12) -> (109.1, 32)
  line L3 (109.1, 32) -> (69.1, 32)
sketch "Skizze6 (15)" plane through (0, 0, 268) normal (0, 0, 1) x (1, 0, 0) in component "Rear_thread_plate_bottom_0.73"
  circle A0 centre (252.9, 22) radius 1.5
  circle A1 centre (228.9, 22) radius 1.5
  circle A2 centre (240.9, 22) radius 2.1
  line L0 (220.9, 32) -> (220.9, 12)
  line L1 (220.9, 12) -> (260.9, 12)
  line L2 (260.9, 12) -> (260.9, 32)
  line L3 (260.9, 32) -> (220.9, 32)
sketch "Skizze6 (16)" plane through (0, 0, 268) normal (0, 0, 1) x (1, 0, 0) in component "Rear_thread_plate_top_0.27"
  circle A0 centre (101.1, 538) radius 1.5
  circle A1 centre (77.1, 538) radius 1.5
  circle A2 centre (89.1, 538) radius 2.1
  line L0 (69.1, 548) -> (69.1, 528)
  line L1 (69.1, 528) -> (109.1, 528)
  line L2 (109.1, 528) -> (109.1, 548)
  line L3 (109.1, 548) -> (69.1, 548)
sketch "Skizze6 (17)" plane through (0, 0, 268) normal (0, 0, 1) x (1, 0, 0) in component "Rear_thread_plate_top_0.73"
  circle A0 centre (252.9, 538) radius 1.5
  circle A1 centre (228.9, 538) radius 1.5
  circle A2 centre (240.9, 538) radius 2.1
  line L0 (220.9, 548) -> (220.9, 528)
  line L1 (220.9, 528) -> (260.9, 528)
  line L2 (260.9, 528) -> (260.9, 548)
  line L3 (260.9, 548) -> (220.9, 548)
component "Side_left" placed x (1, 0, 0) y (0, 1, 0) z (0, 0, 1) at (0, 0, 0)
component "Side_right" placed x (1, 0, 0) y (0, 1, 0) z (0, 0, 1) at (0, 0, 0)
component "Bottom" placed x (1, 0, 0) y (0, 1, 0) z (0, 0, 1) at (0, 0, 0)
component "Top" placed x (1, 0, 0) y (0, 1, 0) z (0, 0, 1) at (0, 0, 0)
component "Baffle" placed x (1, 0, 0) y (0, 1, 0) z (0, 0, 1) at (0, 0, 0)
component "Rear_removable" placed x (1, 0, 0) y (0, 1, 0) z (0, 0, 1) at (0, 0, 0)
component "Baffle_inner_lamination" placed x (1, 0, 0) y (0, 1, 0) z (0, 0, 1) at (0, 0, 0)
component "LF_steel_backing_ring_candidate" placed x (1, 0, 0) y (0, 1, 0) z (0, 0, 1) at (0, 0, 0)
component "Rear_cleat_left" placed x (1, 0, 0) y (0, 1, 0) z (0, 0, 1) at (0, 0, 0)
component "Rear_cleat_right" placed x (1, 0, 0) y (0, 1, 0) z (0, 0, 1) at (0, 0, 0)
component "Rear_cleat_bottom" placed x (1, 0, 0) y (0, 1, 0) z (0, 0, 1) at (0, 0, 0)
component "Rear_cleat_top" placed x (1, 0, 0) y (0, 1, 0) z (0, 0, 1) at (0, 0, 0)